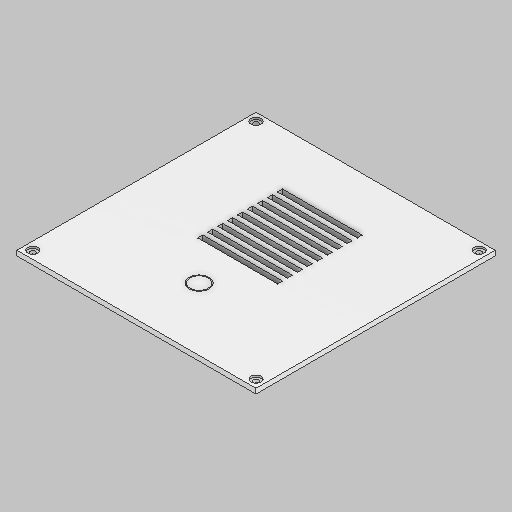
# Autodesk Inventor part: Armadura_superior
Saved by Autodesk Inventor 2027 (Build 310192000, 192)
## iProperties
Created: 2026-11-23
Part Number: Armadura_superior
Material: Genérico
Document SubType Name: Modeling
Designer: Alexander
Density: 1 g/cm^3
Appearance: Valor por defecto
Author: Alexander
Autodesk Inventor part; units mm, degrees
ref_plane "YZ Plane" through (0, 0, 0) normal (1, 0, 0) x (0, 1, 0)
ref_plane "XZ Plane" through (0, 0, 0) normal (0, 1, 0) x (-1, 0, 0)
ref_plane "XY Plane" through (0, 0, 0) normal (0, 0, 1) x (1, 0, 0)
sketch "Boceto1" plane through (0, 0, 0) normal (0, 1, 0) x (-1, 0, 0)
  circle A0 centre (-102.6457, 146.1654) radius 2.5
  circle A1 centre (-102.6457, 146.1654) radius 2.5
  circle A2 centre (121.3543, 146.1654) radius 2.5
  circle A3 centre (121.3543, 146.1654) radius 2.5
  circle A4 centre (-102.6457, -77.8346) radius 2.5
  circle A5 centre (-102.6457, -77.8346) radius 2.5
  circle A6 centre (121.3543, -77.8346) radius 2.5
  circle A7 centre (121.3543, -77.8346) radius 2.5
  line L0 (-110.6457, 154.1654) -> (-110.6457, -85.8346)
  line L1 (129.3543, 154.1654) -> (129.3543, -85.8346)
  line L2 (-110.6457, 154.1654) -> (129.3543, 154.1654)
  line L3 (129.3543, 154.1654) -> (129.3543, -85.8346)
  line L4 (129.3543, -85.8346) -> (-110.6457, -85.8346)
  line L5 (-110.6457, -85.8346) -> (-110.6457, 154.1654)
  line L6 (-105.6457, 34.1654) -> (-100.6457, 34.1654)
  line L7 (-100.6457, 34.1654) -> (-100.6457, 94.1654)
  line L8 (-100.6457, 94.1654) -> (-105.6457, 94.1654)
  line L9 (-105.6457, 94.1654) -> (-105.6457, 34.1654)
  line L10 (-105.6457, 34.1654) -> (-100.6457, 34.1654)
  line L11 (-100.6457, 34.1654) -> (-100.6457, -25.8346)
  line L12 (-100.6457, -25.8346) -> (-105.6457, -25.8346)
  line L13 (-105.6457, -25.8346) -> (-105.6457, 34.1654)
  line L14 (119.3543, 94.1654) -> (124.3543, 94.1654)
  line L15 (124.3543, 94.1654) -> (124.3543, 34.1654)
  line L16 (124.3543, 34.1654) -> (119.3543, 34.1654)
  line L17 (119.3543, 34.1654) -> (119.3543, 94.1654)
  line L18 (119.3543, 34.1654) -> (124.3543, 34.1654)
  line L19 (124.3543, 34.1654) -> (124.3543, -25.8346)
  line L20 (124.3543, -25.8346) -> (119.3543, -25.8346)
  line L21 (119.3543, -25.8346) -> (119.3543, 34.1654)
  line L22 (9.3543, -80.8346) -> (-50.6457, -80.8346)
  line L23 (-50.6457, -80.8346) -> (-50.6457, -75.8346)
  line L24 (-50.6457, -75.8346) -> (9.3543, -75.8346)
  line L25 (9.3543, -75.8346) -> (9.3543, -80.8346)
  line L26 (9.3543, -80.8346) -> (69.3543, -80.8346)
  line L27 (69.3543, -80.8346) -> (69.3543, -75.8346)
  line L28 (69.3543, -75.8346) -> (9.3543, -75.8346)
  line L29 (9.3543, -75.8346) -> (9.3543, -80.8346)
  line L30 (9.3543, 144.1654) -> (-50.6457, 144.1654)
  line L31 (-50.6457, 144.1654) -> (-50.6457, 149.1654)
  line L32 (-50.6457, 149.1654) -> (9.3543, 149.1654)
  line L33 (9.3543, 149.1654) -> (9.3543, 144.1654)
  line L34 (9.3543, 144.1654) -> (69.3543, 144.1654)
  line L35 (69.3543, 144.1654) -> (69.3543, 149.1654)
  line L36 (69.3543, 149.1654) -> (9.3543, 149.1654)
  line L37 (9.3543, 149.1654) -> (9.3543, 144.1654)
  point P0 (0, 0)
  point P1 (9.3543, 34.1654)
  point P2 (121.8543, 34.1654)
  dimension "d0" = 5
  dimension "d1" = 60
  dimension "d2" = 5
  dimension "d3" = 60
  dimension "d4" = 5
  dimension "d5" = 60
  dimension "d6" = 5
  dimension "d7" = 60
  dimension "d8" = 60
  dimension "d9" = 5
  dimension "d10" = 60
  dimension "d11" = 5
  dimension "d12" = 60
  dimension "d13" = 5
  constraints: 76 end point, 18 parallel, 9 horizontal, 9 perpendicular, 8 centre point, 4 coincident, 3 point on line, 1 midpoint
  measures "d0" distance of L8.end L7.end
  measures "d1" distance of L7.end L6.end
  measures "d2" distance between parallel lines of L0 L9
  measures "d3" distance of L10.end L11.end
  measures "d4" distance between parallel lines of L15 L1
  measures "d5" distance from line of point (121.854, 34.165) L14
  measures "d6" distance between parallel lines of L15 L17
  measures "d7" distance of L18.end L19.end
  measures "d8" distance of L23.end L24.end
  measures "d9" distance of L22.end L23.end
  measures "d10" distance of L28.end L27.end
  measures "d11" distance between parallel lines of L4 L26
  measures "d12" distance of L36.end L35.end
  measures "d13" distance between parallel lines of L2 L32
extrude "Extrusión1" add sketch "Boceto1" along normal blind 5 contours L2 L1 L4 L0 | L9 L8 L7 L6 | L6 L11 L12 L13 | L14 L15 L16 L17 | L16 L19 L20 L21 | L22 L23 L24 L25 | L25 L28 L27 L26 | L30 L31 L32 L33 | L33 L36 L35 L34
extrude "Extrusión2" add sketch "Boceto1" against normal blind 5 contours L9 L8 L7 L6 | L6 L11 L12 L13 | L14 L15 L16 L17 | L16 L19 L20 L21 | L22 L23 L24 L25 | L25 L28 L27 L26 | L30 L31 L32 L33 | L33 L36 L35 L34
sketch "Boceto2" plane through (0, 5, 0) normal (0, 1, 0) x (1, 0, 0)
  line L0 (-49.3543, 32.3835) -> (30.6457, 32.3835)
  line L1 (30.6457, 32.3835) -> (30.6457, 27.3835)
  line L2 (30.6457, 27.3835) -> (-49.3543, 27.3835)
  line L3 (-49.3543, 27.3835) -> (-49.3543, 32.3835)
  line L4 (110.6457, -154.1654) -> (110.6457, 85.8346) projected
  line L5 (-49.3543, 22.3835) -> (30.6457, 22.3835)
  line L6 (30.6457, 17.3835) -> (-49.3543, 17.3835)
  line L7 (-49.3543, 17.3835) -> (-49.3543, 22.3835)
  line L8 (30.6457, 22.3835) -> (30.6457, 17.3835)
  line L9 (-49.3543, 12.3835) -> (30.6457, 12.3835)
  line L10 (30.6457, 7.3835) -> (-49.3543, 7.3835)
  line L11 (-49.3543, 7.3835) -> (-49.3543, 12.3835)
  line L12 (30.6457, 12.3835) -> (30.6457, 7.3835)
  line L13 (-49.3543, 2.3835) -> (30.6457, 2.3835)
  line L14 (30.6457, -2.6165) -> (-49.3543, -2.6165)
  line L15 (-49.3543, -2.6165) -> (-49.3543, 2.3835)
  line L16 (30.6457, 2.3835) -> (30.6457, -2.6165)
  line L17 (-49.3543, -7.6165) -> (30.6457, -7.6165)
  line L18 (30.6457, -12.6165) -> (-49.3543, -12.6165)
  line L19 (-49.3543, -12.6165) -> (-49.3543, -7.6165)
  line L20 (30.6457, -7.6165) -> (30.6457, -12.6165)
  line L21 (-49.3543, -17.6165) -> (30.6457, -17.6165)
  line L22 (30.6457, -22.6165) -> (-49.3543, -22.6165)
  line L23 (-49.3543, -22.6165) -> (-49.3543, -17.6165)
  line L24 (30.6457, -17.6165) -> (30.6457, -22.6165)
  line L25 (-49.3543, -27.6165) -> (30.6457, -27.6165)
  line L26 (30.6457, -32.6165) -> (-49.3543, -32.6165)
  line L27 (-49.3543, -32.6165) -> (-49.3543, -27.6165)
  line L28 (30.6457, -27.6165) -> (30.6457, -32.6165)
  line L29 (-49.3543, -37.6165) -> (30.6457, -37.6165)
  line L30 (30.6457, -42.6165) -> (-49.3543, -42.6165)
  line L31 (-49.3543, -42.6165) -> (-49.3543, -37.6165)
  line L32 (30.6457, -37.6165) -> (30.6457, -42.6165)
  line L33 (-49.3543, -47.6165) -> (30.6457, -47.6165)
  line L34 (30.6457, -52.6165) -> (-49.3543, -52.6165)
  line L35 (-49.3543, -52.6165) -> (-49.3543, -47.6165)
  line L36 (30.6457, -47.6165) -> (30.6457, -52.6165)
  circle A0 centre (-9.3543, -91.2523) radius 10
  circle A1 centre (-9.3543, -91.2523) radius 8.9851
  point P0 (0, 0)
  dimension "d18" = 80
  dimension "d19" = 5
  dimension "d20" = 80
  dimension "d23" = 10
  dimension "d28" = 20
  constraints: 72 end point, 2 centre point, 2 parallel, 1 coincident, 1 collinear, 1 horizontal, 1 perpendicular, 1 vertical, 63 other
  measures "d18" distance between parallel lines of L1 L3
  measures "d19" distance of L2.end L0.start
  measures "d20" distance between parallel lines of L1 L4
  measures "d23" distance of L0.start L5.start
  measures "d28" diameter of A0
extrude "Extrusión3" cut sketch "Boceto2" against normal blind 5
sketch "Boceto3" plane through (0, 5, 0) normal (0, 1, 0) x (1, 0, 0)
  circle A0 centre (-121.3543, 77.8346) radius 2.5 projected
  circle A1 centre (-121.3543, 77.8346) radius 5
  circle A2 centre (102.6457, 77.8346) radius 2.5 projected
  circle A3 centre (102.6457, 77.8346) radius 5
  circle A4 centre (102.6457, -146.1654) radius 2.5 projected
  circle A5 centre (102.6457, -146.1654) radius 5
  circle A6 centre (-121.3543, -146.1654) radius 2.5 projected
  circle A7 centre (-121.3543, -146.1654) radius 5
  point P0 (0, 0)
  dimension "d31" = 10
  dimension "d32" = 10
  dimension "d33" = 10
  dimension "d34" = 10
  constraints: 4 centre point, 4 coincident
  measures "d31" diameter of A1
  measures "d32" diameter of A3
  measures "d33" diameter of A5
  measures "d34" diameter of A7
extrude "Extrusión4" cut sketch "Boceto3" against normal blind 2
